TRACO_V1_MONTAGEM (Autodesk Fusion 360 design; units mm, degrees)
part number: 2026-11-01-23-15-29-808
part number: 2026-11-02-14-41-37-280
part number: 2026-11-02-14-41-39-982
part number: 2026-11-02-14-41-41-367
part number: 2026-11-02-14-41-42-819
part number: 2026-11-02-14-41-44-231
part number: 2026-11-02-14-41-45-607
part number: 2026-11-02-14-41-48-442
part number: 2026-11-02-14-41-50-376
part number: 2026-11-02-14-41-50-902
part number: 2026-11-02-14-41-53-478
part number: 2026-11-02-14-41-56-020
part number: 2026-11-02-14-41-56-416
part number: 2026-11-02-14-41-56-793
part number: 2026-11-02-14-41-57-170
part number: 2026-11-02-14-41-57-514
part number: 2026-11-02-14-41-58-004
part number: 2026-11-02-14-41-58-526
part number: 2026-11-02-14-41-59-088
part number: 2026-11-02-14-41-59-616
part number: 2026-11-02-14-42-00-111
part number: 2026-11-02-14-42-00-347
part number: 2026-11-02-14-42-00-588
part number: 2026-11-02-14-42-00-835
part number: 2026-11-02-14-42-01-065
part number: 2026-11-02-14-42-01-515
part number: 2026-11-02-14-42-03-148
part number: 2026-11-02-14-42-03-482
part number: 2026-11-02-14-42-04-686
part number: 2026-11-02-14-42-05-056
part number: 2026-11-02-14-42-05-439
part number: 2026-11-02-14-42-05-847
part number: 2026-11-02-14-42-06-639
part number: 2026-11-02-14-42-06-859
part number: 2026-11-02-14-42-07-483
part number: 2026-11-02-14-42-07-711
part number: 2026-11-02-14-42-08-351
part number: 2026-11-02-14-42-09-563
part number: 2026-11-02-14-42-10-826
Autodesk Fusion 360 part; units mm, degrees
(part 1 of 2)
sketch "Esboço1" plane through (0, 0, 0) normal (0, 0, 1) x (1, 0, 0) in component "TRACO V1 01 base compacta"
  line L0 (-120, -40) -> (-74, -40)
  line L1 (-74, -40) -> (-74, -74)
  line L2 (-74, -74) -> (74, -74)
  line L3 (74, -74) -> (74, 74)
  line L4 (74, 74) -> (-74, 74)
  line L5 (-74, 74) -> (-74, 40)
  line L6 (-74, 40) -> (-120, 40)
  line L7 (-120, 40) -> (-120, -40)
  circle A0 centre (0, 0) radius 4.25
  circle A1 centre (-60, -60) radius 3.2
  circle A2 centre (-60, 60) radius 3.2
  circle A3 centre (60, -60) radius 3.2
  circle A4 centre (60, 60) radius 3.2
  circle A5 centre (-28, -28) radius 2.6
  circle A6 centre (-28, 28) radius 2.6
  circle A7 centre (28, -28) radius 2.6
  circle A8 centre (28, 28) radius 2.6
  circle A9 centre (-75, -30) radius 2.6
  circle A10 centre (-75, 30) radius 2.6
extrude "Extrusão1" add sketch "Esboço1" along normal blind 10 makes body 1 in component "TRACO V1 01 base compacta"
sketch "Esboço1 (2)" plane through (0, 0, 0) normal (0, 0, 1) x (1, 0, 0) in component "TRACO V1 02 mancal inferior"
  line L0 (-38, -38) -> (38, -38)
  line L1 (38, -38) -> (38, 38)
  line L2 (38, 38) -> (-38, 38)
  line L3 (-38, 38) -> (-38, -38)
  circle A0 centre (0, 0) radius 11.075
  circle A1 centre (-28, -28) radius 2.6
  circle A2 centre (-28, 28) radius 2.6
  circle A3 centre (28, -28) radius 2.6
  circle A4 centre (28, 28) radius 2.6
extrude "Extrusão1'" add sketch "Esboço1 (2)" along normal blind 9 separate body makes body 2 in component "TRACO V1 02 mancal inferior"
sketch "Esboço1 (3)" plane through (0, 0, 0) normal (0, 0, 1) x (1, 0, 0) in component "TRACO V1 02a retentor mancal inferior"
  line L0 (-38, -38) -> (38, -38)
  line L1 (38, -38) -> (38, 38)
  line L2 (38, 38) -> (-38, 38)
  line L3 (-38, 38) -> (-38, -38)
  circle A0 centre (0, 0) radius 4.25
  circle A1 centre (-28, -28) radius 2.6
  circle A2 centre (-28, 28) radius 2.6
  circle A3 centre (28, -28) radius 2.6
  circle A4 centre (28, 28) radius 2.6
extrude "Extrusão1''" add sketch "Esboço1 (3)" along normal blind 3 separate body makes body 3 in component "TRACO V1 02a retentor mancal inferior"
sketch "Esboço1 (4)" plane through (0, 0, 0) normal (0, 0, 1) x (1, 0, 0) in component "TRACO V1 03a retentor mancal superior"
  line L0 (-38, -38) -> (38, -38)
  line L1 (38, -38) -> (38, 38)
  line L2 (38, 38) -> (-38, 38)
  line L3 (-38, 38) -> (-38, -38)
  circle A0 centre (0, 0) radius 4.25
  circle A1 centre (-28, -28) radius 2.6
  circle A2 centre (-28, 28) radius 2.6
  circle A3 centre (28, -28) radius 2.6
  circle A4 centre (28, 28) radius 2.6
extrude "Extrusão1'''" add sketch "Esboço1 (4)" along normal blind 3 separate body makes body 4 in component "TRACO V1 03a retentor mancal superior"
sketch "Esboço1 (5)" plane through (0, 0, 0) normal (0, 0, 1) x (1, 0, 0) in component "TRACO V1 03 mancal superior"
  line L0 (-38, -38) -> (38, -38)
  line L1 (38, -38) -> (38, 38)
  line L2 (38, 38) -> (-38, 38)
  line L3 (-38, 38) -> (-38, -38)
  circle A0 centre (0, 0) radius 11.075
  circle A1 centre (-28, -28) radius 2.6
  circle A2 centre (-28, 28) radius 2.6
  circle A3 centre (28, -28) radius 2.6
  circle A4 centre (28, 28) radius 2.6
extrude "Extrusão1''''" add sketch "Esboço1 (5)" along normal blind 9 separate body makes body 5 in component "TRACO V1 03 mancal superior"
sketch "Esboço1 (6)" plane through (0, 0, 0) normal (0, 0, 1) x (1, 0, 0) in component "TRACO V1 04 coluna espaçadora 1"
  line L0 (7, 0) -> (6.7615, 1.8117)
  line L1 (6.7615, 1.8117) -> (6.0622, 3.5)
  line L2 (6.0622, 3.5) -> (4.9497, 4.9497)
  line L3 (4.9497, 4.9497) -> (3.5, 6.0622)
  line L4 (3.5, 6.0622) -> (1.8117, 6.7615)
  line L5 (1.8117, 6.7615) -> (0, 7)
  line L6 (0, 7) -> (-1.8117, 6.7615)
  line L7 (-1.8117, 6.7615) -> (-3.5, 6.0622)
  line L8 (-3.5, 6.0622) -> (-4.9497, 4.9497)
  line L9 (-4.9497, 4.9497) -> (-6.0622, 3.5)
  line L10 (-6.0622, 3.5) -> (-6.7615, 1.8117)
  line L11 (-6.7615, 1.8117) -> (-7, 0)
  line L12 (-7, 0) -> (-6.7615, -1.8117)
  line L13 (-6.7615, -1.8117) -> (-6.0622, -3.5)
  line L14 (-6.0622, -3.5) -> (-4.9497, -4.9497)
  line L15 (-4.9497, -4.9497) -> (-3.5, -6.0622)
  line L16 (-3.5, -6.0622) -> (-1.8117, -6.7615)
  line L17 (-1.8117, -6.7615) -> (0, -7)
  line L18 (0, -7) -> (1.8117, -6.7615)
  line L19 (1.8117, -6.7615) -> (3.5, -6.0622)
  line L20 (3.5, -6.0622) -> (4.9497, -4.9497)
  line L21 (4.9497, -4.9497) -> (6.0622, -3.5)
  line L22 (6.0622, -3.5) -> (6.7615, -1.8117)
  line L23 (6.7615, -1.8117) -> (7, 0)
  circle A0 centre (0, 0) radius 2.6
extrude "Extrusão1'''''" add sketch "Esboço1 (6)" along normal blind 25 separate body makes body 6 in component "TRACO V1 04 coluna espaçadora 1"
sketch "Esboço1 (7)" plane through (0, 0, 0) normal (0, 0, 1) x (1, 0, 0) in component "TRACO V1 04 coluna espaçadora 2"
  line L0 (7, 0) -> (6.7615, 1.8117)
  line L1 (6.7615, 1.8117) -> (6.0622, 3.5)
  line L2 (6.0622, 3.5) -> (4.9497, 4.9497)
  line L3 (4.9497, 4.9497) -> (3.5, 6.0622)
  line L4 (3.5, 6.0622) -> (1.8117, 6.7615)
  line L5 (1.8117, 6.7615) -> (0, 7)
  line L6 (0, 7) -> (-1.8117, 6.7615)
  line L7 (-1.8117, 6.7615) -> (-3.5, 6.0622)
  line L8 (-3.5, 6.0622) -> (-4.9497, 4.9497)
  line L9 (-4.9497, 4.9497) -> (-6.0622, 3.5)
  line L10 (-6.0622, 3.5) -> (-6.7615, 1.8117)
  line L11 (-6.7615, 1.8117) -> (-7, 0)
  line L12 (-7, 0) -> (-6.7615, -1.8117)
  line L13 (-6.7615, -1.8117) -> (-6.0622, -3.5)
  line L14 (-6.0622, -3.5) -> (-4.9497, -4.9497)
  line L15 (-4.9497, -4.9497) -> (-3.5, -6.0622)
  line L16 (-3.5, -6.0622) -> (-1.8117, -6.7615)
  line L17 (-1.8117, -6.7615) -> (0, -7)
  line L18 (0, -7) -> (1.8117, -6.7615)
  line L19 (1.8117, -6.7615) -> (3.5, -6.0622)
  line L20 (3.5, -6.0622) -> (4.9497, -4.9497)
  line L21 (4.9497, -4.9497) -> (6.0622, -3.5)
  line L22 (6.0622, -3.5) -> (6.7615, -1.8117)
  line L23 (6.7615, -1.8117) -> (7, 0)
  circle A0 centre (0, 0) radius 2.6
extrude "Extrusão1''''''" add sketch "Esboço1 (7)" along normal blind 25 separate body makes body 7 in component "TRACO V1 04 coluna espaçadora 2"
sketch "Esboço1 (8)" plane through (0, 0, 0) normal (0, 0, 1) x (1, 0, 0) in component "TRACO V1 04 coluna espaçadora 3"
  line L0 (7, 0) -> (6.7615, 1.8117)
  line L1 (6.7615, 1.8117) -> (6.0622, 3.5)
  line L2 (6.0622, 3.5) -> (4.9497, 4.9497)
  line L3 (4.9497, 4.9497) -> (3.5, 6.0622)
  line L4 (3.5, 6.0622) -> (1.8117, 6.7615)
  line L5 (1.8117, 6.7615) -> (0, 7)
  line L6 (0, 7) -> (-1.8117, 6.7615)
  line L7 (-1.8117, 6.7615) -> (-3.5, 6.0622)
  line L8 (-3.5, 6.0622) -> (-4.9497, 4.9497)
  line L9 (-4.9497, 4.9497) -> (-6.0622, 3.5)
  line L10 (-6.0622, 3.5) -> (-6.7615, 1.8117)
  line L11 (-6.7615, 1.8117) -> (-7, 0)
  line L12 (-7, 0) -> (-6.7615, -1.8117)
  line L13 (-6.7615, -1.8117) -> (-6.0622, -3.5)
  line L14 (-6.0622, -3.5) -> (-4.9497, -4.9497)
  line L15 (-4.9497, -4.9497) -> (-3.5, -6.0622)
  line L16 (-3.5, -6.0622) -> (-1.8117, -6.7615)
  line L17 (-1.8117, -6.7615) -> (0, -7)
  line L18 (0, -7) -> (1.8117, -6.7615)
  line L19 (1.8117, -6.7615) -> (3.5, -6.0622)
  line L20 (3.5, -6.0622) -> (4.9497, -4.9497)
  line L21 (4.9497, -4.9497) -> (6.0622, -3.5)
  line L22 (6.0622, -3.5) -> (6.7615, -1.8117)
  line L23 (6.7615, -1.8117) -> (7, 0)
  circle A0 centre (0, 0) radius 2.6
extrude "Extrusão1'''''''" add sketch "Esboço1 (8)" along normal blind 25 separate body makes body 8 in component "TRACO V1 04 coluna espaçadora 3"
sketch "Esboço1 (9)" plane through (0, 0, 0) normal (0, 0, 1) x (1, 0, 0) in component "TRACO V1 04 coluna espaçadora 4"
  line L0 (7, 0) -> (6.7615, 1.8117)
  line L1 (6.7615, 1.8117) -> (6.0622, 3.5)
  line L2 (6.0622, 3.5) -> (4.9497, 4.9497)
  line L3 (4.9497, 4.9497) -> (3.5, 6.0622)
  line L4 (3.5, 6.0622) -> (1.8117, 6.7615)
  line L5 (1.8117, 6.7615) -> (0, 7)
  line L6 (0, 7) -> (-1.8117, 6.7615)
  line L7 (-1.8117, 6.7615) -> (-3.5, 6.0622)
  line L8 (-3.5, 6.0622) -> (-4.9497, 4.9497)
  line L9 (-4.9497, 4.9497) -> (-6.0622, 3.5)
  line L10 (-6.0622, 3.5) -> (-6.7615, 1.8117)
  line L11 (-6.7615, 1.8117) -> (-7, 0)
  line L12 (-7, 0) -> (-6.7615, -1.8117)
  line L13 (-6.7615, -1.8117) -> (-6.0622, -3.5)
  line L14 (-6.0622, -3.5) -> (-4.9497, -4.9497)
  line L15 (-4.9497, -4.9497) -> (-3.5, -6.0622)
  line L16 (-3.5, -6.0622) -> (-1.8117, -6.7615)
  line L17 (-1.8117, -6.7615) -> (0, -7)
  line L18 (0, -7) -> (1.8117, -6.7615)
  line L19 (1.8117, -6.7615) -> (3.5, -6.0622)
  line L20 (3.5, -6.0622) -> (4.9497, -4.9497)
  line L21 (4.9497, -4.9497) -> (6.0622, -3.5)
  line L22 (6.0622, -3.5) -> (6.7615, -1.8117)
  line L23 (6.7615, -1.8117) -> (7, 0)
  circle A0 centre (0, 0) radius 2.6
extrude "Extrusão1''''''''" add sketch "Esboço1 (9)" along normal blind 25 separate body makes body 9 in component "TRACO V1 04 coluna espaçadora 4"
sketch "Esboço1 (10)" plane through (0, 0, 0) normal (0, 0, 1) x (1, 0, 0) in component "TRACO V1 05 plataforma giratoria"
  line L0 (58, 0) -> (57.5038, 7.5705)
  line L1 (57.5038, 7.5705) -> (56.0237, 15.0115)
  line L2 (56.0237, 15.0115) -> (53.585, 22.1956)
  line L3 (53.585, 22.1956) -> (50.2295, 29)
  line L4 (50.2295, 29) -> (46.0145, 35.3082)
  line L5 (46.0145, 35.3082) -> (41.0122, 41.0122)
  line L6 (41.0122, 41.0122) -> (35.3082, 46.0145)
  line L7 (35.3082, 46.0145) -> (29, 50.2295)
  line L8 (29, 50.2295) -> (22.1956, 53.585)
  line L9 (22.1956, 53.585) -> (15.0115, 56.0237)
  line L10 (15.0115, 56.0237) -> (7.5705, 57.5038)
  line L11 (7.5705, 57.5038) -> (0, 58)
  line L12 (0, 58) -> (-7.5705, 57.5038)
  line L13 (-7.5705, 57.5038) -> (-15.0115, 56.0237)
  line L14 (-15.0115, 56.0237) -> (-22.1956, 53.585)
  line L15 (-22.1956, 53.585) -> (-29, 50.2295)
  line L16 (-29, 50.2295) -> (-35.3082, 46.0145)
  line L17 (-35.3082, 46.0145) -> (-41.0122, 41.0122)
  line L18 (-41.0122, 41.0122) -> (-46.0145, 35.3082)
  line L19 (-46.0145, 35.3082) -> (-50.2295, 29)
  line L20 (-50.2295, 29) -> (-53.585, 22.1956)
  line L21 (-53.585, 22.1956) -> (-56.0237, 15.0115)
  line L22 (-56.0237, 15.0115) -> (-57.5038, 7.5705)
  line L23 (-57.5038, 7.5705) -> (-58, 0)
  line L24 (-58, 0) -> (-57.5038, -7.5705)
  line L25 (-57.5038, -7.5705) -> (-56.0237, -15.0115)
  line L26 (-56.0237, -15.0115) -> (-53.585, -22.1956)
  line L27 (-53.585, -22.1956) -> (-50.2295, -29)
  line L28 (-50.2295, -29) -> (-46.0145, -35.3082)
  line L29 (-46.0145, -35.3082) -> (-41.0122, -41.0122)
  line L30 (-41.0122, -41.0122) -> (-35.3082, -46.0145)
  line L31 (-35.3082, -46.0145) -> (-29, -50.2295)
  line L32 (-29, -50.2295) -> (-22.1956, -53.585)
  line L33 (-22.1956, -53.585) -> (-15.0115, -56.0237)
  line L34 (-15.0115, -56.0237) -> (-7.5705, -57.5038)
  line L35 (-7.5705, -57.5038) -> (0, -58)
  line L36 (0, -58) -> (7.5705, -57.5038)
  line L37 (7.5705, -57.5038) -> (15.0115, -56.0237)
  line L38 (15.0115, -56.0237) -> (22.1956, -53.585)
  line L39 (22.1956, -53.585) -> (29, -50.2295)
  line L40 (29, -50.2295) -> (35.3082, -46.0145)
  line L41 (35.3082, -46.0145) -> (41.0122, -41.0122)
  line L42 (41.0122, -41.0122) -> (46.0145, -35.3082)
  line L43 (46.0145, -35.3082) -> (50.2295, -29)
  line L44 (50.2295, -29) -> (53.585, -22.1956)
  line L45 (53.585, -22.1956) -> (56.0237, -15.0115)
  line L46 (56.0237, -15.0115) -> (57.5038, -7.5705)
  line L47 (57.5038, -7.5705) -> (58, 0)
  circle A0 centre (0, 0) radius 4.075
  circle A1 centre (9.525, 0) radius 1.7
  circle A2 centre (4.7625, 8.2489) radius 1.7
  circle A3 centre (-4.7625, 8.2489) radius 1.7
  circle A4 centre (-9.525, 0) radius 1.7
  circle A5 centre (-4.7625, -8.2489) radius 1.7
  circle A6 centre (4.7625, -8.2489) radius 1.7
  circle A7 centre (-37, -22) radius 2.6
  circle A8 centre (-37, 22) radius 2.6
  circle A9 centre (37, -22) radius 2.6
  circle A10 centre (37, 22) radius 2.6
extrude "Extrusão1'''''''''" add sketch "Esboço1 (10)" along normal blind 12 separate body makes body 10 in component "TRACO V1 05 plataforma giratoria"
sketch "Esboço1 (11)" plane through (0, 0, 0) normal (0, 0, 1) x (1, 0, 0) in component "TRACO V1 06 torre direita"
  line L0 (-50, -64) -> (48, -64)
  line L1 (48, -64) -> (48, -30)
  line L2 (48, -30) -> (34, 26)
  line L3 (34, 26) -> (17, 55)
  line L4 (17, 55) -> (-27, 55)
  line L5 (-27, 55) -> (-48, 24)
  line L6 (-48, 24) -> (-50, -64)
  circle A0 centre (0, 18) radius 11.075
  circle A1 centre (-37, -43) radius 2.6
  circle A2 centre (37, -43) radius 2.6
  circle A3 centre (-36, -16) radius 2.1
  circle A4 centre (36, -16) radius 2.1
  circle A5 centre (-26, -31) radius 2.6
  circle A6 centre (-26, 19) radius 2.6
  circle A7 centre (0, -12) radius 2.6
extrude "Extrusão1''''''''''" add sketch "Esboço1 (11)" along normal blind 9 separate body makes body 11 in component "TRACO V1 06 torre direita"
sketch "Esboço1 (12)" plane through (0, 0, 0) normal (0, 0, 1) x (1, 0, 0) in component "TRACO V1 06 torre esquerda"
  line L0 (-50, -64) -> (48, -64)
  line L1 (48, -64) -> (48, -30)
  line L2 (48, -30) -> (34, 26)
  line L3 (34, 26) -> (17, 55)
  line L4 (17, 55) -> (-27, 55)
  line L5 (-27, 55) -> (-48, 24)
  line L6 (-48, 24) -> (-50, -64)
  circle A0 centre (0, 18) radius 11.075
  circle A1 centre (-37, -43) radius 2.6
  circle A2 centre (37, -43) radius 2.6
  circle A3 centre (-36, -16) radius 2.1
  circle A4 centre (36, -16) radius 2.1
  circle A5 centre (-26, -31) radius 2.6
  circle A6 centre (-26, 19) radius 2.6
  circle A7 centre (0, -12) radius 2.6
extrude "Extrusão1'''''''''''" add sketch "Esboço1 (12)" along normal blind 9 separate body makes body 12 in component "TRACO V1 06 torre esquerda"
sketch "Esboço1 (13)" plane through (0, 0, 0) normal (0, 0, 1) x (1, 0, 0) in component "TRACO V1 07 suporte motor base"
  line L0 (-35, -35) -> (35, -35)
  line L1 (35, -35) -> (35, 35)
  line L2 (35, 35) -> (-35, 35)
  line L3 (-35, 35) -> (-35, -35)
  circle A0 centre (-15.5, -15.5) radius 1.7
  circle A1 centre (-15.5, 15.5) radius 1.7
  circle A2 centre (15.5, -15.5) radius 1.7
  circle A3 centre (15.5, 15.5) radius 1.7
  circle A4 centre (0, 0) radius 11.5
  line L4 (-5, -32.6) -> (5, -32.6)
  arc A5 (5, -32.6) -> (5, -27.4) centre (5, -30) ccw
  line L5 (5, -27.4) -> (-5, -27.4)
  arc A6 (-5, -27.4) -> (-5, -32.6) centre (-5, -30) ccw
  line L6 (-5, -30) -> (5, -30) construction
  line L7 (-5, 27.4) -> (5, 27.4)
  arc A7 (5, 27.4) -> (5, 32.6) centre (5, 30) ccw
  line L8 (5, 32.6) -> (-5, 32.6)
  arc A8 (-5, 32.6) -> (-5, 27.4) centre (-5, 30) ccw
  line L9 (-5, 30) -> (5, 30) construction
  constraint tangent L4 A5
  constraint tangent A5 L5
  constraint tangent L5 A6
  constraint tangent L4 A6
  constraint parallel L4 L5
  constraint tangent L7 A7
  constraint tangent A7 L8
  constraint tangent L8 A8
  constraint tangent L7 A8
  constraint parallel L7 L8
extrude "Extrusão1''''''''''''" add sketch "Esboço1 (13)" along normal blind 8 separate body makes body 13 in component "TRACO V1 07 suporte motor base"
sketch "Esboço1 (14)" plane through (0, 0, 0) normal (0, 0, 1) x (1, 0, 0) in component "TRACO V1 08 suporte motor ombro"
  line L0 (-41, -34) -> (41, -34)
  line L1 (41, -34) -> (41, 34)
  line L2 (41, 34) -> (-41, 34)
  line L3 (-41, 34) -> (-41, -34)
  circle A0 centre (-15.5, -15.5) radius 1.7
  circle A1 centre (-15.5, 15.5) radius 1.7
  circle A2 centre (15.5, -15.5) radius 1.7
  circle A3 centre (15.5, 15.5) radius 1.7
  circle A4 centre (0, 0) radius 11.5
  line L4 (30, -27.6) -> (40, -27.6)
  arc A5 (40, -27.6) -> (40, -22.4) centre (40, -25) ccw
  line L5 (40, -22.4) -> (30, -22.4)
  arc A6 (30, -22.4) -> (30, -27.6) centre (30, -25) ccw
  line L6 (30, -25) -> (40, -25) construction
  line L7 (30, 22.4) -> (40, 22.4)
  arc A7 (40, 22.4) -> (40, 27.6) centre (40, 25) ccw
  line L8 (40, 27.6) -> (30, 27.6)
  arc A8 (30, 27.6) -> (30, 22.4) centre (30, 25) ccw
  line L9 (30, 25) -> (40, 25) construction
  constraint tangent L4 A5
  constraint tangent A5 L5
  constraint tangent L5 A6
  constraint tangent L4 A6
  constraint parallel L4 L5
  constraint tangent L7 A7
  constraint tangent A7 L8
  constraint tangent L8 A8
  constraint tangent L7 A8
  constraint parallel L7 L8
extrude "Extrusão1'''''''''''''" add sketch "Esboço1 (14)" along normal blind 8 separate body contours L0 L1 L2 L3 L4 A5 L5 A6 L7 A7 L8 A8 makes body 14 in component "TRACO V1 08 suporte motor ombro"
sketch "Esboço1 (15)" plane through (0, 0, 0) normal (0, 0, 1) x (1, 0, 0) in component "TRACO V1 09 suporte motor cotovelo"
  line L0 (-41, -34) -> (41, -34)
  line L1 (41, -34) -> (41, 34)
  line L2 (41, 34) -> (-41, 34)
  line L3 (-41, 34) -> (-41, -34)
  circle A0 centre (-15.5, -15.5) radius 1.7
  circle A1 centre (-15.5, 15.5) radius 1.7
  circle A2 centre (15.5, -15.5) radius 1.7
  circle A3 centre (15.5, 15.5) radius 1.7
  circle A4 centre (0, 0) radius 11.5
  line L4 (-30, -2.6) -> (-20, -2.6)
  arc A5 (-20, -2.6) -> (-20, 2.6) centre (-20, 0) ccw
  line L5 (-20, 2.6) -> (-30, 2.6)
  arc A6 (-30, 2.6) -> (-30, -2.6) centre (-30, 0) ccw
  line L6 (-30, 0) -> (-20, 0) construction
  line L7 (20, -2.6) -> (30, -2.6)
  arc A7 (30, -2.6) -> (30, 2.6) centre (30, 0) ccw
  line L8 (30, 2.6) -> (20, 2.6)
  arc A8 (20, 2.6) -> (20, -2.6) centre (20, 0) ccw
  line L9 (20, 0) -> (30, 0) construction
  constraint tangent L4 A5
  constraint tangent A5 L5
  constraint tangent L5 A6
  constraint tangent L4 A6
  constraint parallel L4 L5
  constraint tangent L7 A7
  constraint tangent A7 L8
  constraint tangent L8 A8
  constraint tangent L7 A8
  constraint parallel L7 L8
extrude "Extrusão1''''''''''''''" add sketch "Esboço1 (15)" along normal blind 8 separate body makes body 15 in component "TRACO V1 09 suporte motor cotovelo"
sketch "Esboço1 (16)" plane through (0, 0, 0) normal (0, 0, 1) x (1, 0, 0) in component "TRACO V1 10 braco superior direita"
  line L0 (-23, -20) -> (18, -20)
  line L1 (18, -20) -> (102, -13)
  line L2 (102, -13) -> (182, -18)
  line L3 (182, -18) -> (223, -18)
  line L4 (223, -18) -> (223, 18)
  line L5 (223, 18) -> (182, 18)
  line L6 (182, 18) -> (102, 13)
  line L7 (102, 13) -> (18, 20)
  line L8 (18, 20) -> (-23, 20)
  line L9 (-23, 20) -> (-23, -20)
  circle A0 centre (0, 0) radius 4.125
  circle A1 centre (200, 0) radius 11.075
  circle A2 centre (35, 0) radius 2.6
  circle A3 centre (85, 0) radius 2.6
  circle A4 centre (165, 0) radius 2.6
  circle A5 centre (9.525, 0) radius 1.7
  circle A6 centre (4.7625, 8.2489) radius 1.7
  circle A7 centre (-4.7625, 8.2489) radius 1.7
  circle A8 centre (-9.525, 0) radius 1.7
  circle A9 centre (-4.7625, -8.2489) radius 1.7
  circle A10 centre (4.7625, -8.2489) radius 1.7
extrude "Extrusão1'''''''''''''''" add sketch "Esboço1 (16)" along normal blind 8 separate body makes body 16 in component "TRACO V1 10 braco superior direita"
sketch "Esboço1 (17)" plane through (0, 0, 0) normal (0, 0, 1) x (1, 0, 0) in component "TRACO V1 11 antebraco direita"
  line L0 (-22, -17) -> (18, -17)
  line L1 (18, -17) -> (100, -11)
  line L2 (100, -11) -> (181, -16)
  line L3 (181, -16) -> (222, -16)
  line L4 (222, -16) -> (222, 16)
  line L5 (222, 16) -> (181, 16)
  line L6 (181, 16) -> (100, 11)
  line L7 (100, 11) -> (18, 17)
  line L8 (18, 17) -> (-22, 17)
  line L9 (-22, 17) -> (-22, -17)
  circle A0 centre (0, 0) radius 4.125
  circle A1 centre (200, 0) radius 11.075
  circle A2 centre (35, 0) radius 2.6
  circle A3 centre (165, 0) radius 2.6
  circle A4 centre (9.525, 0) radius 1.7
  circle A5 centre (4.7625, 8.2489) radius 1.7
  circle A6 centre (-4.7625, 8.2489) radius 1.7
  circle A7 centre (-9.525, 0) radius 1.7
  circle A8 centre (-4.7625, -8.2489) radius 1.7
  circle A9 centre (4.7625, -8.2489) radius 1.7
extrude "Extrusão1''''''''''''''''" add sketch "Esboço1 (17)" along normal blind 8 separate body makes body 17 in component "TRACO V1 11 antebraco direita"
sketch "Esboço1 (18)" plane through (0, 0, 0) normal (0, 0, 1) x (1, 0, 0) in component "TRACO V1 10 braco superior esquerda"
  line L0 (-23, -20) -> (18, -20)
  line L1 (18, -20) -> (102, -13)
  line L2 (102, -13) -> (182, -18)
  line L3 (182, -18) -> (223, -18)
  line L4 (223, -18) -> (223, 18)
  line L5 (223, 18) -> (182, 18)
  line L6 (182, 18) -> (102, 13)
  line L7 (102, 13) -> (18, 20)
  line L8 (18, 20) -> (-23, 20)
  line L9 (-23, 20) -> (-23, -20)
  circle A0 centre (0, 0) radius 4.125
  circle A1 centre (200, 0) radius 11.075
  circle A2 centre (35, 0) radius 2.6
  circle A3 centre (85, 0) radius 2.6
  circle A4 centre (165, 0) radius 2.6
  circle A5 centre (9.525, 0) radius 1.7
  circle A6 centre (4.7625, 8.2489) radius 1.7
  circle A7 centre (-4.7625, 8.2489) radius 1.7
  circle A8 centre (-9.525, 0) radius 1.7
  circle A9 centre (-4.7625, -8.2489) radius 1.7
  circle A10 centre (4.7625, -8.2489) radius 1.7
extrude "Extrusão1'''''''''''''''''" add sketch "Esboço1 (18)" along normal blind 8 separate body makes body 18 in component "TRACO V1 10 braco superior esquerda"
sketch "Esboço1 (19)" plane through (0, 0, 0) normal (0, 0, 1) x (1, 0, 0) in component "TRACO V1 11 antebraco esquerda"
  line L0 (-22, -17) -> (18, -17)
  line L1 (18, -17) -> (100, -11)
  line L2 (100, -11) -> (181, -16)
  line L3 (181, -16) -> (222, -16)
  line L4 (222, -16) -> (222, 16)
  line L5 (222, 16) -> (181, 16)
  line L6 (181, 16) -> (100, 11)
  line L7 (100, 11) -> (18, 17)
  line L8 (18, 17) -> (-22, 17)
  line L9 (-22, 17) -> (-22, -17)
  circle A0 centre (0, 0) radius 4.125
  circle A1 centre (200, 0) radius 11.075
  circle A2 centre (35, 0) radius 2.6
  circle A3 centre (165, 0) radius 2.6
  circle A4 centre (9.525, 0) radius 1.7
  circle A5 centre (4.7625, 8.2489) radius 1.7
  circle A6 centre (-4.7625, 8.2489) radius 1.7
  circle A7 centre (-9.525, 0) radius 1.7
  circle A8 centre (-4.7625, -8.2489) radius 1.7
  circle A9 centre (4.7625, -8.2489) radius 1.7
extrude "Extrusão1''''''''''''''''''" add sketch "Esboço1 (19)" along normal blind 8 separate body makes body 19 in component "TRACO V1 11 antebraco esquerda"
sketch "Esboço1 (20)" plane through (0, 0, 0) normal (0, 0, 1) x (1, 0, 0) in component "TRACO V1 12 haste paralela superior"
  line L0 (-13, -7) -> (213, -7)
  line L1 (213, -7) -> (213, 7)
  line L2 (213, 7) -> (-13, 7)
  line L3 (-13, 7) -> (-13, -7)
  circle A0 centre (0, 0) radius 2.65
  circle A1 centre (200, 0) radius 2.65
extrude "Extrusão1'''''''''''''''''''" add sketch "Esboço1 (20)" along normal blind 7 separate body makes body 20 in component "TRACO V1 12 haste paralela superior"
sketch "Esboço1 (21)" plane through (0, 0, 0) normal (0, 0, 1) x (1, 0, 0) in component "TRACO V1 13 haste paralela inferior"
  line L0 (-13, -7) -> (213, -7)
  line L1 (213, -7) -> (213, 7)
  line L2 (213, 7) -> (-13, 7)
  line L3 (-13, 7) -> (-13, -7)
  circle A0 centre (0, 0) radius 2.65
  circle A1 centre (200, 0) radius 2.65
extrude "Extrusão1''''''''''''''''''''" add sketch "Esboço1 (21)" along normal blind 7 separate body makes body 21 in component "TRACO V1 13 haste paralela inferior"
sketch "Esboço1 (22)" plane through (0, 0, 0) normal (0, 0, 1) x (1, 0, 0) in component "TRACO V1 14 ancora fixa haste"
  line L0 (-13, -45) -> (13, -45)
  line L1 (13, -45) -> (13, 45)
  line L2 (13, 45) -> (-13, 45)
  line L3 (-13, 45) -> (-13, -45)
  circle A0 centre (0, 0) radius 4.15
  circle A1 centre (0, 30) radius 2.65
  circle A2 centre (0, -30) radius 2.65
extrude "Extrusão1'''''''''''''''''''''" add sketch "Esboço1 (22)" along normal blind 8 separate body makes body 22 in component "TRACO V1 14 ancora fixa haste"
sketch "Esboço1 (23)" plane through (0, 0, 0) normal (0, 0, 1) x (1, 0, 0) in component "TRACO V1 15 balancim cotovelo"
  line L0 (-18, -20) -> (18, -20)
  line L1 (18, -20) -> (18, 50)
  line L2 (18, 50) -> (-18, 50)
  line L3 (-18, 50) -> (-18, -20)
  circle A0 centre (0, 0) radius 11.075
  circle A1 centre (0, 30) radius 2.65
extrude "Extrusão1''''''''''''''''''''''" add sketch "Esboço1 (23)" along normal blind 8 separate body makes body 23 in component "TRACO V1 15 balancim cotovelo"
sketch "Esboço1 (24)" plane through (0, 0, 0) normal (0, 0, 1) x (1, 0, 0) in component "TRACO V1 16 cabeca vertical"
  line L0 (-17, -65) -> (17, -65)
  line L1 (17, -65) -> (17, 51)
  line L2 (17, 51) -> (-17, 51)
  line L3 (-17, 51) -> (-17, -65)
  circle A0 centre (0, 0) radius 4.15
  circle A1 centre (0, 30) radius 2.65
  circle A2 centre (-12, -50) radius 2.15
  circle A3 centre (-12, -20) radius 2.15
  circle A4 centre (12, -50) radius 2.15
  circle A5 centre (12, -20) radius 2.15
  circle A6 centre (9.525, 0) radius 1.7
  circle A7 centre (4.7625, 8.2489) radius 1.7
  circle A8 centre (-4.7625, 8.2489) radius 1.7
  circle A9 centre (-9.525, 0) radius 1.7
  circle A10 centre (-4.7625, -8.2489) radius 1.7
  circle A11 centre (4.7625, -8.2489) radius 1.7
extrude "Extrusão1'''''''''''''''''''''''" add sketch "Esboço1 (24)" along normal blind 10 separate body makes body 24 in component "TRACO V1 16 cabeca vertical"
sketch "Esboço1 (25)" plane through (0, 0, 0) normal (0, 0, 1) x (1, 0, 0) in component "TRACO V1 17 porta caneta 10mm"
  line L0 (15, 0) -> (14.8717, 1.9579)
  line L1 (14.8717, 1.9579) -> (14.4889, 3.8823)
  line L2 (14.4889, 3.8823) -> (13.8582, 5.7403)
  line L3 (13.8582, 5.7403) -> (12.9904, 7.5)
  line L4 (12.9904, 7.5) -> (11.9003, 9.1314)
  line L5 (11.9003, 9.1314) -> (10.6066, 10.6066)
  line L6 (10.6066, 10.6066) -> (9.1314, 11.9003)
  line L7 (9.1314, 11.9003) -> (7.5, 12.9904)
  line L8 (7.5, 12.9904) -> (5.7403, 13.8582)
  line L9 (5.7403, 13.8582) -> (3.8823, 14.4889)
  line L10 (3.8823, 14.4889) -> (1.9579, 14.8717)
  line L11 (1.9579, 14.8717) -> (0, 15)
  line L12 (0, 15) -> (-1.9579, 14.8717)
  line L13 (-1.9579, 14.8717) -> (-3.8823, 14.4889)
  line L14 (-3.8823, 14.4889) -> (-5.7403, 13.8582)
  line L15 (-5.7403, 13.8582) -> (-7.5, 12.9904)
  line L16 (-7.5, 12.9904) -> (-9.1314, 11.9003)
  line L17 (-9.1314, 11.9003) -> (-10.6066, 10.6066)
  line L18 (-10.6066, 10.6066) -> (-11.9003, 9.1314)
  line L19 (-11.9003, 9.1314) -> (-12.9904, 7.5)
  line L20 (-12.9904, 7.5) -> (-13.8582, 5.7403)
  line L21 (-13.8582, 5.7403) -> (-14.4889, 3.8823)
  line L22 (-14.4889, 3.8823) -> (-14.8717, 1.9579)
  line L23 (-14.8717, 1.9579) -> (-15, 0)
  line L24 (-15, 0) -> (-14.8717, -1.9579)
  line L25 (-14.8717, -1.9579) -> (-14.4889, -3.8823)
  line L26 (-14.4889, -3.8823) -> (-13.8582, -5.7403)
  line L27 (-13.8582, -5.7403) -> (-12.9904, -7.5)
  line L28 (-12.9904, -7.5) -> (-11.9003, -9.1314)
  line L29 (-11.9003, -9.1314) -> (-10.6066, -10.6066)
  line L30 (-10.6066, -10.6066) -> (-9.1314, -11.9003)
  line L31 (-9.1314, -11.9003) -> (-7.5, -12.9904)
  line L32 (-7.5, -12.9904) -> (-5.7403, -13.8582)
  line L33 (-5.7403, -13.8582) -> (-3.8823, -14.4889)
  line L34 (-3.8823, -14.4889) -> (-1.9579, -14.8717)
  line L35 (-1.9579, -14.8717) -> (0, -15)
  line L36 (0, -15) -> (1.9579, -14.8717)
  line L37 (1.9579, -14.8717) -> (3.8823, -14.4889)
  line L38 (3.8823, -14.4889) -> (5.7403, -13.8582)
  line L39 (5.7403, -13.8582) -> (7.5, -12.9904)
  line L40 (7.5, -12.9904) -> (9.1314, -11.9003)
  line L41 (9.1314, -11.9003) -> (10.6066, -10.6066)
  line L42 (10.6066, -10.6066) -> (11.9003, -9.1314)
  line L43 (11.9003, -9.1314) -> (12.9904, -7.5)
  line L44 (12.9904, -7.5) -> (13.8582, -5.7403)
  line L45 (13.8582, -5.7403) -> (14.4889, -3.8823)
  line L46 (14.4889, -3.8823) -> (14.8717, -1.9579)
  line L47 (14.8717, -1.9579) -> (15, 0)
  circle A0 centre (0, 0) radius 5.4
extrude "Extrusão1''''''''''''''''''''''''" add sketch "Esboço1 (25)" along normal blind 80 separate body makes body 25 in component "TRACO V1 17 porta caneta 10mm"
sketch "Esboço2" plane through (0, 0, 0) normal (0, 0, 1) x (1, 0, 0) in component "TRACO V1 17 porta caneta 10mm"
  line L0 (-16, -20) -> (16, -20)
  line L1 (16, -20) -> (16, -10)
  line L2 (16, -10) -> (-16, -10)
  line L3 (-16, -10) -> (-16, -20)
extrude "Extrusão2" add sketch "Esboço2" along normal blind 80 bodies 25 in component "TRACO V1 17 porta caneta 10mm"
sketch "Esboço3" plane through (0, 0, 0) normal (0, 1, 0) x (1, 0, 0) in component "TRACO V1 17 porta caneta 10mm"
  circle A0 centre (-12, -35) radius 2.15
extrude "Extrusão3" cut sketch "Esboço3" along normal blind 25 bodies 25 in component "TRACO V1 17 porta caneta 10mm"
sketch "Esboço4" plane through (0, 0, 0) normal (0, 1, 0) x (1, 0, 0) in component "TRACO V1 17 porta caneta 10mm"
  circle A0 centre (-12, -65) radius 2.15
extrude "Extrusão4" cut sketch "Esboço4" along normal blind 25 bodies 25 in component "TRACO V1 17 porta caneta 10mm"
sketch "Esboço5" plane through (0, 0, 0) normal (0, 1, 0) x (1, 0, 0) in component "TRACO V1 17 porta caneta 10mm"
  circle A0 centre (12, -35) radius 2.15
extrude "Extrusão5" cut sketch "Esboço5" along normal blind 25 bodies 25 in component "TRACO V1 17 porta caneta 10mm"
sketch "Esboço6" plane through (0, 0, 0) normal (0, 1, 0) x (1, 0, 0) in component "TRACO V1 17 porta caneta 10mm"
  circle A0 centre (12, -65) radius 2.15
extrude "Extrusão6" cut sketch "Esboço6" along normal blind 25 bodies 25 in component "TRACO V1 17 porta caneta 10mm"
sketch "Esboço1 (26)" plane through (0, 0, 0) normal (0, 0, 1) x (1, 0, 0) in component "TRACO V1 18 carenagem superior direita"
  line L0 (-16, -23) -> (35, -24)
  line L1 (35, -24) -> (155, -19)
  line L2 (155, -19) -> (213, -22)
  line L3 (213, -22) -> (213, 22)
  line L4 (213, 22) -> (155, 19)
  line L5 (155, 19) -> (35, 24)
  line L6 (35, 24) -> (-16, 23)
  line L7 (-16, 23) -> (-16, -23)
  circle A0 centre (12, 0) radius 2.1
  circle A1 centre (188, 0) radius 2.1
extrude "Extrusão1'''''''''''''''''''''''''" add sketch "Esboço1 (26)" along normal blind 3 separate body makes body 26 in component "TRACO V1 18 carenagem superior direita"
sketch "Esboço1 (27)" plane through (0, 0, 0) normal (0, 0, 1) x (1, 0, 0) in component "TRACO V1 20 carenagem base"
  line L0 (70, 0) -> (69.4011, 9.1368)
  line L1 (69.4011, 9.1368) -> (67.6148, 18.1173)
  line L2 (67.6148, 18.1173) -> (64.6716, 26.7878)
  line L3 (64.6716, 26.7878) -> (60.6218, 35)
  line L4 (60.6218, 35) -> (55.5347, 42.6133)
  line L5 (55.5347, 42.6133) -> (49.4975, 49.4975)
  line L6 (49.4975, 49.4975) -> (42.6133, 55.5347)
  line L7 (42.6133, 55.5347) -> (35, 60.6218)
  line L8 (35, 60.6218) -> (26.7878, 64.6716)
  line L9 (26.7878, 64.6716) -> (18.1173, 67.6148)
  line L10 (18.1173, 67.6148) -> (9.1368, 69.4011)
  line L11 (9.1368, 69.4011) -> (0, 70)
  line L12 (0, 70) -> (-9.1368, 69.4011)
  line L13 (-9.1368, 69.4011) -> (-18.1173, 67.6148)
  line L14 (-18.1173, 67.6148) -> (-26.7878, 64.6716)
  line L15 (-26.7878, 64.6716) -> (-35, 60.6218)
  line L16 (-35, 60.6218) -> (-42.6133, 55.5347)
  line L17 (-42.6133, 55.5347) -> (-49.4975, 49.4975)
  line L18 (-49.4975, 49.4975) -> (-55.5347, 42.6133)
  line L19 (-55.5347, 42.6133) -> (-60.6218, 35)
  line L20 (-60.6218, 35) -> (-64.6716, 26.7878)
  line L21 (-64.6716, 26.7878) -> (-67.6148, 18.1173)
  line L22 (-67.6148, 18.1173) -> (-69.4011, 9.1368)
  line L23 (-69.4011, 9.1368) -> (-70, 0)
  line L24 (-70, 0) -> (-69.4011, -9.1368)
  line L25 (-69.4011, -9.1368) -> (-67.6148, -18.1173)
  line L26 (-67.6148, -18.1173) -> (-64.6716, -26.7878)
  line L27 (-64.6716, -26.7878) -> (-60.6218, -35)
  line L28 (-60.6218, -35) -> (-55.5347, -42.6133)
  line L29 (-55.5347, -42.6133) -> (-49.4975, -49.4975)
  line L30 (-49.4975, -49.4975) -> (-42.6133, -55.5347)
  line L31 (-42.6133, -55.5347) -> (-35, -60.6218)
  line L32 (-35, -60.6218) -> (-26.7878, -64.6716)
  line L33 (-26.7878, -64.6716) -> (-18.1173, -67.6148)
  line L34 (-18.1173, -67.6148) -> (-9.1368, -69.4011)
  line L35 (-9.1368, -69.4011) -> (0, -70)
  line L36 (0, -70) -> (9.1368, -69.4011)
  line L37 (9.1368, -69.4011) -> (18.1173, -67.6148)
  line L38 (18.1173, -67.6148) -> (26.7878, -64.6716)
  line L39 (26.7878, -64.6716) -> (35, -60.6218)
  line L40 (35, -60.6218) -> (42.6133, -55.5347)
  line L41 (42.6133, -55.5347) -> (49.4975, -49.4975)
  line L42 (49.4975, -49.4975) -> (55.5347, -42.6133)
  line L43 (55.5347, -42.6133) -> (60.6218, -35)
  line L44 (60.6218, -35) -> (64.6716, -26.7878)
  line L45 (64.6716, -26.7878) -> (67.6148, -18.1173)
  line L46 (67.6148, -18.1173) -> (69.4011, -9.1368)
  line L47 (69.4011, -9.1368) -> (70, 0)
  circle A0 centre (0, 0) radius 16
extrude "Extrusão1''''''''''''''''''''''''''" add sketch "Esboço1 (27)" along normal blind 4 separate body makes body 27 in component "TRACO V1 20 carenagem base"
sketch "Esboço1 (28)" plane through (0, 0, 0) normal (0, 0, 1) x (1, 0, 0) in component "TRACO V1 21 tampa correia ombro"
  line L0 (-18, -18) -> (20, -18)
  line L1 (20, -18) -> (65, -39)
  line L2 (65, -39) -> (88, -39)
  line L3 (88, -39) -> (88, 39)
  line L4 (88, 39) -> (65, 39)
  line L5 (65, 39) -> (20, 18)
  line L6 (20, 18) -> (-18, 18)
  line L7 (-18, 18) -> (-18, -18)
  circle A0 centre (-5, 0) radius 2.1
  circle A1 centre (77, -29) radius 2.1
  circle A2 centre (77, 29) radius 2.1
extrude "Extrusão1'''''''''''''''''''''''''''" add sketch "Esboço1 (28)" along normal blind 3 separate body makes body 28 in component "TRACO V1 21 tampa correia ombro"
sketch "Esboço1 (29)" plane through (0, 0, 0) normal (0, 0, 1) x (1, 0, 0) in component "TRACO V1 22 tampa correia cotovelo"
  line L0 (-18, -18) -> (22, -20)
  line L1 (22, -20) -> (135, -38)
  line L2 (135, -38) -> (164, -38)
  line L3 (164, -38) -> (164, 38)
  line L4 (164, 38) -> (135, 38)
  line L5 (135, 38) -> (22, 20)
  line L6 (22, 20) -> (-18, 18)
  line L7 (-18, 18) -> (-18, -18)
  circle A0 centre (-5, 0) radius 2.1
  circle A1 centre (150, -28) radius 2.1
  circle A2 centre (150, 28) radius 2.1
extrude "Extrusão1''''''''''''''''''''''''''''" add sketch "Esboço1 (29)" along normal blind 3 separate body makes body 29 in component "TRACO V1 22 tampa correia cotovelo"
sketch "Esboço1 (30)" plane through (0, 0, 0) normal (0, 0, 1) x (1, 0, 0) in component "TRACO V1 REF motor base 17HS4401"
  line L0 (-21, -21) -> (21, -21)
  line L1 (21, -21) -> (21, 21)
  line L2 (21, 21) -> (-21, 21)
  line L3 (-21, 21) -> (-21, -21)
extrude "Extrusão1'''''''''''''''''''''''''''''" add sketch "Esboço1 (30)" along normal blind 40 separate body makes body 30 in component "TRACO V1 REF motor base 17HS4401"
sketch "Esboço1 (31)" plane through (0, 0, 0) normal (0, 0, 1) x (1, 0, 0) in component "TRACO V1 REF eixo motor base 5mm"
  line L0 (2.5, 0) -> (2.4148, 0.647)
  line L1 (2.4148, 0.647) -> (2.1651, 1.25)
  line L2 (2.1651, 1.25) -> (1.7678, 1.7678)
  line L3 (1.7678, 1.7678) -> (1.25, 2.1651)
  line L4 (1.25, 2.1651) -> (0.647, 2.4148)
  line L5 (0.647, 2.4148) -> (0, 2.5)
  line L6 (0, 2.5) -> (-0.647, 2.4148)
  line L7 (-0.647, 2.4148) -> (-1.25, 2.1651)
  line L8 (-1.25, 2.1651) -> (-1.7678, 1.7678)
  line L9 (-1.7678, 1.7678) -> (-2.1651, 1.25)
  line L10 (-2.1651, 1.25) -> (-2.4148, 0.647)
  line L11 (-2.4148, 0.647) -> (-2.5, 0)
  line L12 (-2.5, 0) -> (-2.4148, -0.647)
  line L13 (-2.4148, -0.647) -> (-2.1651, -1.25)
  line L14 (-2.1651, -1.25) -> (-1.7678, -1.7678)
  line L15 (-1.7678, -1.7678) -> (-1.25, -2.1651)
  line L16 (-1.25, -2.1651) -> (-0.647, -2.4148)
  line L17 (-0.647, -2.4148) -> (0, -2.5)
  line L18 (0, -2.5) -> (0.647, -2.4148)
  line L19 (0.647, -2.4148) -> (1.25, -2.1651)
  line L20 (1.25, -2.1651) -> (1.7678, -1.7678)
  line L21 (1.7678, -1.7678) -> (2.1651, -1.25)
  line L22 (2.1651, -1.25) -> (2.4148, -0.647)
  line L23 (2.4148, -0.647) -> (2.5, 0)
extrude "Extrusão1''''''''''''''''''''''''''''''" add sketch "Esboço1 (31)" along normal blind 24 separate body makes body 31 in component "TRACO V1 REF eixo motor base 5mm"
sketch "Esboço1 (32)" plane through (0, 0, 0) normal (0, 0, 1) x (1, 0, 0) in component "TRACO V1 REF motor ombro 17HS4401"
  line L0 (-21, -21) -> (21, -21)
  line L1 (21, -21) -> (21, 21)
  line L2 (21, 21) -> (-21, 21)
  line L3 (-21, 21) -> (-21, -21)
extrude "Extrusão1'''''''''''''''''''''''''''''''" add sketch "Esboço1 (32)" along normal blind 40 separate body makes body 32 in component "TRACO V1 REF motor ombro 17HS4401"
sketch "Esboço1 (33)" plane through (0, 0, 0) normal (0, 0, 1) x (1, 0, 0) in component "TRACO V1 REF eixo motor ombro 5mm"
  line L0 (2.5, 0) -> (2.4148, 0.647)
  line L1 (2.4148, 0.647) -> (2.1651, 1.25)
  line L2 (2.1651, 1.25) -> (1.7678, 1.7678)
  line L3 (1.7678, 1.7678) -> (1.25, 2.1651)
  line L4 (1.25, 2.1651) -> (0.647, 2.4148)
  line L5 (0.647, 2.4148) -> (0, 2.5)
  line L6 (0, 2.5) -> (-0.647, 2.4148)
  line L7 (-0.647, 2.4148) -> (-1.25, 2.1651)
  line L8 (-1.25, 2.1651) -> (-1.7678, 1.7678)
  line L9 (-1.7678, 1.7678) -> (-2.1651, 1.25)
  line L10 (-2.1651, 1.25) -> (-2.4148, 0.647)
  line L11 (-2.4148, 0.647) -> (-2.5, 0)
  line L12 (-2.5, 0) -> (-2.4148, -0.647)
  line L13 (-2.4148, -0.647) -> (-2.1651, -1.25)
  line L14 (-2.1651, -1.25) -> (-1.7678, -1.7678)
  line L15 (-1.7678, -1.7678) -> (-1.25, -2.1651)
  line L16 (-1.25, -2.1651) -> (-0.647, -2.4148)
  line L17 (-0.647, -2.4148) -> (0, -2.5)
  line L18 (0, -2.5) -> (0.647, -2.4148)
  line L19 (0.647, -2.4148) -> (1.25, -2.1651)
  line L20 (1.25, -2.1651) -> (1.7678, -1.7678)
  line L21 (1.7678, -1.7678) -> (2.1651, -1.25)
  line L22 (2.1651, -1.25) -> (2.4148, -0.647)
  line L23 (2.4148, -0.647) -> (2.5, 0)
extrude "Extrusão1''''''''''''''''''''''''''''''''" add sketch "Esboço1 (33)" along normal blind 24 separate body makes body 33 in component "TRACO V1 REF eixo motor ombro 5mm"
sketch "Esboço1 (34)" plane through (0, 0, 0) normal (0, 0, 1) x (1, 0, 0) in component "TRACO V1 REF motor cotovelo 17HS4401"
  line L0 (-21, -21) -> (21, -21)
  line L1 (21, -21) -> (21, 21)
  line L2 (21, 21) -> (-21, 21)
  line L3 (-21, 21) -> (-21, -21)
extrude "Extrusão1'''''''''''''''''''''''''''''''''" add sketch "Esboço1 (34)" along normal blind 40 separate body makes body 34 in component "TRACO V1 REF motor cotovelo 17HS4401"
sketch "Esboço1 (35)" plane through (0, 0, 0) normal (0, 0, 1) x (1, 0, 0) in component "TRACO V1 REF eixo motor cotovelo 5mm"
  line L0 (2.5, 0) -> (2.4148, 0.647)
  line L1 (2.4148, 0.647) -> (2.1651, 1.25)
  line L2 (2.1651, 1.25) -> (1.7678, 1.7678)
  line L3 (1.7678, 1.7678) -> (1.25, 2.1651)
  line L4 (1.25, 2.1651) -> (0.647, 2.4148)
  line L5 (0.647, 2.4148) -> (0, 2.5)
  line L6 (0, 2.5) -> (-0.647, 2.4148)
  line L7 (-0.647, 2.4148) -> (-1.25, 2.1651)
  line L8 (-1.25, 2.1651) -> (-1.7678, 1.7678)
  line L9 (-1.7678, 1.7678) -> (-2.1651, 1.25)
  line L10 (-2.1651, 1.25) -> (-2.4148, 0.647)
  line L11 (-2.4148, 0.647) -> (-2.5, 0)
  line L12 (-2.5, 0) -> (-2.4148, -0.647)
  line L13 (-2.4148, -0.647) -> (-2.1651, -1.25)
  line L14 (-2.1651, -1.25) -> (-1.7678, -1.7678)
  line L15 (-1.7678, -1.7678) -> (-1.25, -2.1651)
  line L16 (-1.25, -2.1651) -> (-0.647, -2.4148)
  line L17 (-0.647, -2.4148) -> (0, -2.5)
  line L18 (0, -2.5) -> (0.647, -2.4148)
  line L19 (0.647, -2.4148) -> (1.25, -2.1651)
  line L20 (1.25, -2.1651) -> (1.7678, -1.7678)
  line L21 (1.7678, -1.7678) -> (2.1651, -1.25)
  line L22 (2.1651, -1.25) -> (2.4148, -0.647)
  line L23 (2.4148, -0.647) -> (2.5, 0)
extrude "Extrusão1''''''''''''''''''''''''''''''''''" add sketch "Esboço1 (35)" along normal blind 24 separate body makes body 35 in component "TRACO V1 REF eixo motor cotovelo 5mm"
sketch "Esboço1 (36)" plane through (0, 0, 0) normal (0, 0, 1) x (1, 0, 0) in component "TRACO V1 REF polia J1 100T envelope"
  line L0 (32, 0) -> (31.7262, 4.1768)
  line L1 (31.7262, 4.1768) -> (30.9096, 8.2822)
  line L2 (30.9096, 8.2822) -> (29.5641, 12.2459)
  line L3 (29.5641, 12.2459) -> (27.7128, 16)
  line L4 (27.7128, 16) -> (25.3873, 19.4804)
  line L5 (25.3873, 19.4804) -> (22.6274, 22.6274)
  line L6 (22.6274, 22.6274) -> (19.4804, 25.3873)
  line L7 (19.4804, 25.3873) -> (16, 27.7128)
  line L8 (16, 27.7128) -> (12.2459, 29.5641)
  line L9 (12.2459, 29.5641) -> (8.2822, 30.9096)
  line L10 (8.2822, 30.9096) -> (4.1768, 31.7262)
  line L11 (4.1768, 31.7262) -> (0, 32)
  line L12 (0, 32) -> (-4.1768, 31.7262)
  line L13 (-4.1768, 31.7262) -> (-8.2822, 30.9096)
  line L14 (-8.2822, 30.9096) -> (-12.2459, 29.5641)
  line L15 (-12.2459, 29.5641) -> (-16, 27.7128)
  line L16 (-16, 27.7128) -> (-19.4804, 25.3873)
  line L17 (-19.4804, 25.3873) -> (-22.6274, 22.6274)
  line L18 (-22.6274, 22.6274) -> (-25.3873, 19.4804)
  line L19 (-25.3873, 19.4804) -> (-27.7128, 16)
  line L20 (-27.7128, 16) -> (-29.5641, 12.2459)
  line L21 (-29.5641, 12.2459) -> (-30.9096, 8.2822)
  line L22 (-30.9096, 8.2822) -> (-31.7262, 4.1768)
  line L23 (-31.7262, 4.1768) -> (-32, 0)
  line L24 (-32, 0) -> (-31.7262, -4.1768)
  line L25 (-31.7262, -4.1768) -> (-30.9096, -8.2822)
  line L26 (-30.9096, -8.2822) -> (-29.5641, -12.2459)
  line L27 (-29.5641, -12.2459) -> (-27.7128, -16)
  line L28 (-27.7128, -16) -> (-25.3873, -19.4804)
  line L29 (-25.3873, -19.4804) -> (-22.6274, -22.6274)
  line L30 (-22.6274, -22.6274) -> (-19.4804, -25.3873)
  line L31 (-19.4804, -25.3873) -> (-16, -27.7128)
  line L32 (-16, -27.7128) -> (-12.2459, -29.5641)
  line L33 (-12.2459, -29.5641) -> (-8.2822, -30.9096)
  line L34 (-8.2822, -30.9096) -> (-4.1768, -31.7262)
  line L35 (-4.1768, -31.7262) -> (0, -32)
  line L36 (0, -32) -> (4.1768, -31.7262)
  line L37 (4.1768, -31.7262) -> (8.2822, -30.9096)
  line L38 (8.2822, -30.9096) -> (12.2459, -29.5641)
  line L39 (12.2459, -29.5641) -> (16, -27.7128)
  line L40 (16, -27.7128) -> (19.4804, -25.3873)
  line L41 (19.4804, -25.3873) -> (22.6274, -22.6274)
  line L42 (22.6274, -22.6274) -> (25.3873, -19.4804)
  line L43 (25.3873, -19.4804) -> (27.7128, -16)
  line L44 (27.7128, -16) -> (29.5641, -12.2459)
  line L45 (29.5641, -12.2459) -> (30.9096, -8.2822)
  line L46 (30.9096, -8.2822) -> (31.7262, -4.1768)
  line L47 (31.7262, -4.1768) -> (32, 0)
  circle A0 centre (0, 0) radius 4.1
extrude "Extrusão1'''''''''''''''''''''''''''''''''''" add sketch "Esboço1 (36)" along normal blind 8 separate body makes body 36 in component "TRACO V1 REF polia J1 100T envelope"
sketch "Esboço1 (37)" plane through (0, 0, 0) normal (0, 0, 1) x (1, 0, 0) in component "TRACO V1 REF polia J2 100T envelope"
  line L0 (32, 0) -> (31.7262, 4.1768)
  line L1 (31.7262, 4.1768) -> (30.9096, 8.2822)
  line L2 (30.9096, 8.2822) -> (29.5641, 12.2459)
  line L3 (29.5641, 12.2459) -> (27.7128, 16)
  line L4 (27.7128, 16) -> (25.3873, 19.4804)
  line L5 (25.3873, 19.4804) -> (22.6274, 22.6274)
  line L6 (22.6274, 22.6274) -> (19.4804, 25.3873)
  line L7 (19.4804, 25.3873) -> (16, 27.7128)
  line L8 (16, 27.7128) -> (12.2459, 29.5641)
  line L9 (12.2459, 29.5641) -> (8.2822, 30.9096)
  line L10 (8.2822, 30.9096) -> (4.1768, 31.7262)
  line L11 (4.1768, 31.7262) -> (0, 32)
  line L12 (0, 32) -> (-4.1768, 31.7262)
  line L13 (-4.1768, 31.7262) -> (-8.2822, 30.9096)
  line L14 (-8.2822, 30.9096) -> (-12.2459, 29.5641)
  line L15 (-12.2459, 29.5641) -> (-16, 27.7128)
  line L16 (-16, 27.7128) -> (-19.4804, 25.3873)
  line L17 (-19.4804, 25.3873) -> (-22.6274, 22.6274)
  line L18 (-22.6274, 22.6274) -> (-25.3873, 19.4804)
  line L19 (-25.3873, 19.4804) -> (-27.7128, 16)
  line L20 (-27.7128, 16) -> (-29.5641, 12.2459)
  line L21 (-29.5641, 12.2459) -> (-30.9096, 8.2822)
  line L22 (-30.9096, 8.2822) -> (-31.7262, 4.1768)
  line L23 (-31.7262, 4.1768) -> (-32, 0)
  line L24 (-32, 0) -> (-31.7262, -4.1768)
  line L25 (-31.7262, -4.1768) -> (-30.9096, -8.2822)
  line L26 (-30.9096, -8.2822) -> (-29.5641, -12.2459)
  line L27 (-29.5641, -12.2459) -> (-27.7128, -16)
  line L28 (-27.7128, -16) -> (-25.3873, -19.4804)
  line L29 (-25.3873, -19.4804) -> (-22.6274, -22.6274)
  line L30 (-22.6274, -22.6274) -> (-19.4804, -25.3873)
  line L31 (-19.4804, -25.3873) -> (-16, -27.7128)
  line L32 (-16, -27.7128) -> (-12.2459, -29.5641)
  line L33 (-12.2459, -29.5641) -> (-8.2822, -30.9096)
  line L34 (-8.2822, -30.9096) -> (-4.1768, -31.7262)
  line L35 (-4.1768, -31.7262) -> (0, -32)
  line L36 (0, -32) -> (4.1768, -31.7262)
  line L37 (4.1768, -31.7262) -> (8.2822, -30.9096)
  line L38 (8.2822, -30.9096) -> (12.2459, -29.5641)
  line L39 (12.2459, -29.5641) -> (16, -27.7128)
  line L40 (16, -27.7128) -> (19.4804, -25.3873)
  line L41 (19.4804, -25.3873) -> (22.6274, -22.6274)
  line L42 (22.6274, -22.6274) -> (25.3873, -19.4804)
  line L43 (25.3873, -19.4804) -> (27.7128, -16)
  line L44 (27.7128, -16) -> (29.5641, -12.2459)
  line L45 (29.5641, -12.2459) -> (30.9096, -8.2822)
  line L46 (30.9096, -8.2822) -> (31.7262, -4.1768)
  line L47 (31.7262, -4.1768) -> (32, 0)
  circle A0 centre (0, 0) radius 4.1
extrude "Extrusão1''''''''''''''''''''''''''''''''''''" add sketch "Esboço1 (37)" along normal blind 8 separate body makes body 37 in component "TRACO V1 REF polia J2 100T envelope"
sketch "Esboço1 (38)" plane through (0, 0, 0) normal (0, 0, 1) x (1, 0, 0) in component "TRACO V1 REF polia J3 100T envelope"
  line L0 (32, 0) -> (31.7262, 4.1768)
  line L1 (31.7262, 4.1768) -> (30.9096, 8.2822)
  line L2 (30.9096, 8.2822) -> (29.5641, 12.2459)
  line L3 (29.5641, 12.2459) -> (27.7128, 16)
  line L4 (27.7128, 16) -> (25.3873, 19.4804)
  line L5 (25.3873, 19.4804) -> (22.6274, 22.6274)
  line L6 (22.6274, 22.6274) -> (19.4804, 25.3873)
  line L7 (19.4804, 25.3873) -> (16, 27.7128)
  line L8 (16, 27.7128) -> (12.2459, 29.5641)
  line L9 (12.2459, 29.5641) -> (8.2822, 30.9096)
  line L10 (8.2822, 30.9096) -> (4.1768, 31.7262)
  line L11 (4.1768, 31.7262) -> (0, 32)
  line L12 (0, 32) -> (-4.1768, 31.7262)
  line L13 (-4.1768, 31.7262) -> (-8.2822, 30.9096)
  line L14 (-8.2822, 30.9096) -> (-12.2459, 29.5641)
  line L15 (-12.2459, 29.5641) -> (-16, 27.7128)
  line L16 (-16, 27.7128) -> (-19.4804, 25.3873)
  line L17 (-19.4804, 25.3873) -> (-22.6274, 22.6274)
  line L18 (-22.6274, 22.6274) -> (-25.3873, 19.4804)
  line L19 (-25.3873, 19.4804) -> (-27.7128, 16)
  line L20 (-27.7128, 16) -> (-29.5641, 12.2459)
  line L21 (-29.5641, 12.2459) -> (-30.9096, 8.2822)
  line L22 (-30.9096, 8.2822) -> (-31.7262, 4.1768)
  line L23 (-31.7262, 4.1768) -> (-32, 0)
  line L24 (-32, 0) -> (-31.7262, -4.1768)
  line L25 (-31.7262, -4.1768) -> (-30.9096, -8.2822)
  line L26 (-30.9096, -8.2822) -> (-29.5641, -12.2459)
  line L27 (-29.5641, -12.2459) -> (-27.7128, -16)
  line L28 (-27.7128, -16) -> (-25.3873, -19.4804)
  line L29 (-25.3873, -19.4804) -> (-22.6274, -22.6274)
  line L30 (-22.6274, -22.6274) -> (-19.4804, -25.3873)
  line L31 (-19.4804, -25.3873) -> (-16, -27.7128)
  line L32 (-16, -27.7128) -> (-12.2459, -29.5641)
  line L33 (-12.2459, -29.5641) -> (-8.2822, -30.9096)
  line L34 (-8.2822, -30.9096) -> (-4.1768, -31.7262)
  line L35 (-4.1768, -31.7262) -> (0, -32)
  line L36 (0, -32) -> (4.1768, -31.7262)
  line L37 (4.1768, -31.7262) -> (8.2822, -30.9096)
  line L38 (8.2822, -30.9096) -> (12.2459, -29.5641)
  line L39 (12.2459, -29.5641) -> (16, -27.7128)
  line L40 (16, -27.7128) -> (19.4804, -25.3873)
  line L41 (19.4804, -25.3873) -> (22.6274, -22.6274)
  line L42 (22.6274, -22.6274) -> (25.3873, -19.4804)
  line L43 (25.3873, -19.4804) -> (27.7128, -16)
  line L44 (27.7128, -16) -> (29.5641, -12.2459)
  line L45 (29.5641, -12.2459) -> (30.9096, -8.2822)
  line L46 (30.9096, -8.2822) -> (31.7262, -4.1768)
  line L47 (31.7262, -4.1768) -> (32, 0)
  circle A0 centre (0, 0) radius 4.1
extrude "Extrusão1'''''''''''''''''''''''''''''''''''''" add sketch "Esboço1 (38)" along normal blind 8 separate body makes body 38 in component "TRACO V1 REF polia J3 100T envelope"
component "TRACO V1 01 base compacta" placed x (1, 0, 0) y (0, 1, 0) z (0, 0, 1) at (0, 0, 0)
component "TRACO V1 02 mancal inferior" placed x (1, 0, 0) y (0, 1, 0) z (0, 0, 1) at (0, 0, 10)
component "TRACO V1 02a retentor mancal inferior" placed x (1, 0, 0) y (0, 1, 0) z (0, 0, 1) at (0, 0, 19)
component "TRACO V1 03a retentor mancal superior" placed x (1, 0, 0) y (0, 1, 0) z (0, 0, 1) at (0, 0, 47)
component "TRACO V1 03 mancal superior" placed x (1, 0, 0) y (0, 1, 0) z (0, 0, 1) at (0, 0, 50)
component "TRACO V1 04 coluna espaçadora 1" placed x (1, 0, 0) y (0, 1, 0) z (0, 0, 1) at (28, 28, 22)
component "TRACO V1 04 coluna espaçadora 2" placed x (1, 0, 0) y (0, 1, 0) z (0, 0, 1) at (28, -28, 22)
component "TRACO V1 04 coluna espaçadora 3" placed x (1, 0, 0) y (0, 1, 0) z (0, 0, 1) at (-28, 28, 22)
component "TRACO V1 04 coluna espaçadora 4" placed x (1, 0, 0) y (0, 1, 0) z (0, 0, 1) at (-28, -28, 22)